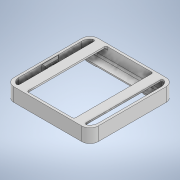
# Autodesk Inventor part: intercom_suport
Saved by Autodesk Inventor 2022.6 (Build 266554000, 554)
## iProperties
Created: 2026-04-23
Part Number: intercom_suport
Material: Generic
Document SubType Name: Modeling
Designer: Dragos Macovei
Density: 1 g/cm^3
Appearance: Default
Author: Dragos Macovei
Autodesk Inventor part; units mm, degrees
ref_plane "YZ Plane" through (0, 0, 0) normal (1, 0, 0) x (0, 1, 0)
ref_plane "XZ Plane" through (0, 0, 0) normal (0, 1, 0) x (-1, 0, 0)
ref_plane "XY Plane" through (0, 0, 0) normal (0, 0, 1) x (1, 0, 0)
sketch "Sketch1" plane through (0, 0, 0) normal (0, 1, 0) x (-1, 0, 0)
  line L0 (40.7008, 47.8646) -> (40.7008, 132.8646)
  line L1 (30.7008, 142.8646) -> (-54.2992, 142.8646)
  line L2 (40.7008, 37.8646) -> (38.7008, 37.8646)
  line L3 (-64.2992, 140.8646) -> (-64.2992, 142.8646)
  line L4 (-64.2992, 132.8646) -> (-64.2992, 47.8646)
  line L5 (-54.2992, 37.8646) -> (30.7008, 37.8646)
  arc A0 (-54.2992, 142.8646) -> (-64.2992, 132.8646) centre (-54.2992, 132.8646) ccw
  arc A1 (-64.2992, 47.8646) -> (-54.2992, 37.8646) centre (-54.2992, 47.8646) ccw
  line L6 (40.7008, 132.8646) -> (40.7008, 132.8646)
  line L7 (30.7008, 142.8646) -> (23.8305, 142.8646)
  arc A2 (40.7008, 132.8646) -> (30.7008, 142.8646) centre (30.7008, 132.8646) ccw
  arc A3 (30.7008, 37.8646) -> (40.7008, 47.8646) centre (30.7008, 47.8646) ccw
  line L8 (37.7008, 129.8646) -> (37.7008, 50.8646)
  line L9 (27.7008, 40.8646) -> (-51.2992, 40.8646)
  line L10 (-61.2992, 50.8646) -> (-61.2992, 93.3869)
  line L11 (-61.2992, 93.3869) -> (-61.2992, 129.8646)
  line L12 (-51.2992, 139.8646) -> (27.7008, 139.8646)
  arc A4 (37.7008, 129.8646) -> (27.7008, 139.8646) centre (27.7008, 129.8646) ccw
  arc A5 (-51.2992, 139.8646) -> (-61.2992, 129.8646) centre (-51.2992, 129.8646) ccw
  arc A6 (-61.2992, 50.8646) -> (-51.2992, 40.8646) centre (-51.2992, 50.8646) ccw
  arc A7 (27.7008, 40.8646) -> (37.7008, 50.8646) centre (27.7008, 50.8646) ccw
  point P0 (-11.7992, 142.8646)
  point P1 (-61.2992, 139.8646)
  dimension "d37" = 10
  dimension "d38" = 10
  dimension "d39" = 105
  dimension "d40" = 105
  dimension "d41" = 10
  dimension "d42" = 10
  dimension "d43" = 3
  dimension "d44" = 3
  dimension "d45" = 3
  dimension "d46" = 3
  dimension "d47" = 10
  constraints: 26 end point, 16 point on circle, 16 tangent, 8 centre point, 8 point on line, 5 perpendicular, 4 vertical, 3 equal radius, 1 horizontal, 1 midpoint
  measures "d37" radius of A0
  measures "d38" radius of A1
  measures "d39" distance between parallel lines of L4 L0
  measures "d40" distance from line of L5 point (-11.799, 142.865)
  measures "d41" radius of A2
  measures "d42" radius of A3
  measures "d43" distance between parallel lines of L1 L12
  measures "d44" distance between parallel lines of L0 L8
  measures "d45" distance between parallel lines of L5 L9
  measures "d46" distance between parallel lines of L4 L10
  measures "d47" radius of A4
extrude "Extrusion1" add sketch "Sketch1" along normal blind 17
sketch "Sketch2" plane through (0, 0, 0) normal (0, -1, 0) x (1, 0, 0)
  line L0 (-30.7008, 142.8646) -> (54.2992, 142.8646) projected
  arc A0 (-30.7008, 142.8646) -> (-40.7008, 132.8646) centre (-30.7008, 132.8646) ccw projected
  line L1 (-40.7008, 47.8646) -> (-40.7008, 132.8646) projected
  arc A1 (-40.7008, 47.8646) -> (-30.7008, 37.8646) centre (-30.7008, 47.8646) ccw projected
  line L2 (54.2992, 37.8646) -> (-30.7008, 37.8646) projected
  arc A2 (54.2992, 37.8646) -> (64.2992, 47.8646) centre (54.2992, 47.8646) ccw projected
  line L3 (64.2992, 132.8646) -> (64.2992, 47.8646) projected
  arc A3 (64.2992, 132.8646) -> (54.2992, 142.8646) centre (54.2992, 132.8646) ccw projected
  line L4 (51.2992, 139.8646) -> (-27.7008, 139.8646) projected
  arc A4 (61.2992, 129.8646) -> (51.2992, 139.8646) centre (51.2992, 129.8646) ccw projected
  line L5 (61.2992, 50.8646) -> (61.2992, 129.8646) projected
  arc A5 (51.2992, 40.8646) -> (61.2992, 50.8646) centre (51.2992, 50.8646) ccw projected
  line L6 (-27.7008, 40.8646) -> (51.2992, 40.8646) projected
  arc A6 (-37.7008, 50.8646) -> (-27.7008, 40.8646) centre (-27.7008, 50.8646) ccw projected
  line L7 (-37.7008, 129.8646) -> (-37.7008, 50.8646) projected
  arc A7 (-27.7008, 139.8646) -> (-37.7008, 129.8646) centre (-27.7008, 129.8646) ccw projected
  line L8 (-30.7008, 142.8646) -> (54.2992, 142.8646)
  line L9 (61.2992, 140.0061) -> (61.2992, 127.8646)
  line L10 (61.2992, 127.8646) -> (-37.7008, 127.8646)
  line L11 (-37.7008, 127.8646) -> (-37.7008, 140.0061)
  line L12 (54.2992, 37.8646) -> (-30.7008, 37.8646)
  line L13 (-40.7008, 52.8646) -> (64.2992, 52.8646)
  point P0 (0, 0)
  point P1 (61.2992, 107.224)
  point P2 (-37.7008, 107.224)
  point P3 (61.2992, 52.8646)
  point P4 (-37.7008, 52.8646)
  dimension "d49" = 15
  dimension "d65" = 0
  dimension "d66" = 15
  constraints: 12 end point, 6 point on circle, 3 parallel, 3 point on line, 2 horizontal, 1 perpendicular
  measures "d49" distance between parallel lines of L10 L8
  measures "d65" distance between parallel lines of L0 L8
  measures "d66" distance between parallel lines of L12 L13
extrude "Extrusion2" add sketch "Sketch2" against normal blind 2 contours A7 L4 A4 L5 L10 L7 | L13 L5 A5 L6 A6 L7
fillet "Fillet1" radius 2 10 edges at (-37.7008, 2, 128.8646) (61.2992, 2, 128.8646) (61.2992, 1, 127.8646) (-37.7008, 1, 127.8646) (61.2992, 9.5, 129.8646) (-37.7008, 9.5, 129.8646) (-37.7008, 2, 51.8646) (61.2992, 2, 51.8646) (61.2992, 9.5, 50.8646) (-37.7008, 9.5, 50.8646)
sketch "Sketch4" plane through (0, 17, 0) normal (0, 1, 0) x (1, 0, 0)
  line L0 (-30.7008, -142.8646) -> (54.2992, -142.8646) projected
  arc A0 (54.2992, -142.8646) -> (64.2992, -132.8646) centre (54.2992, -132.8646) ccw projected
  line L1 (64.2992, -132.8646) -> (64.2992, -47.8646) projected
  arc A1 (64.2992, -47.8646) -> (54.2992, -37.8646) centre (54.2992, -47.8646) ccw projected
  line L2 (54.2992, -37.8646) -> (-30.7008, -37.8646) projected
  arc A2 (-30.7008, -37.8646) -> (-40.7008, -47.8646) centre (-30.7008, -47.8646) ccw projected
  line L3 (-40.7008, -47.8646) -> (-40.7008, -132.8646) projected
  arc A3 (-40.7008, -132.8646) -> (-30.7008, -142.8646) centre (-30.7008, -132.8646) ccw projected
  line L4 (51.2992, -139.8646) -> (-27.7008, -139.8646) projected
  arc A4 (-37.7008, -129.8646) -> (-27.7008, -139.8646) centre (-27.7008, -129.8646) ccw projected
  line L5 (-37.7008, -129.8646) -> (-37.7008, -50.8646) projected
  arc A5 (-27.7008, -40.8646) -> (-37.7008, -50.8646) centre (-27.7008, -50.8646) ccw projected
  line L6 (-27.7008, -40.8646) -> (51.2992, -40.8646) projected
  arc A6 (61.2992, -50.8646) -> (51.2992, -40.8646) centre (51.2992, -50.8646) ccw projected
  line L7 (61.2992, -50.8646) -> (61.2992, -129.8646) projected
  arc A7 (51.2992, -139.8646) -> (61.2992, -129.8646) centre (51.2992, -129.8646) ccw projected
  line L8 (53.2992, -142.8646) -> (41.2992, -142.8646)
  line L9 (41.2992, -142.8646) -> (41.2992, -37.8646)
  line L10 (41.2992, -37.8646) -> (53.2992, -37.8646)
  line L11 (53.2992, -37.8646) -> (53.2992, -142.8646)
  line L12 (-17.7008, -142.8646) -> (-29.7008, -142.8646)
  line L13 (-29.7008, -142.8646) -> (-29.7008, -37.8646)
  line L14 (-29.7008, -37.8646) -> (-17.7008, -37.8646)
  line L15 (-17.7008, -37.8646) -> (-17.7008, -142.8646)
  point P0 (0, 0)
  point P1 (64.2992, -90.3646)
  point P2 (47.2992, -142.8646)
  point P3 (47.2992, -37.8646)
  point P4 (-17.7008, -139.8646)
  point P5 (-17.7008, -40.8646)
  point P6 (-29.7008, -41.0667)
  point P7 (-29.7008, -139.6626)
  point P8 (53.2992, -139.6626)
  point P9 (53.2992, -41.0667)
  point P10 (41.2992, -40.8646)
  point P11 (41.2992, -139.8646)
  dimension "d55" = 23
  dimension "d56" = 23
  dimension "d57" = 12
  dimension "d58" = 12
  dimension "d59" = 0
  dimension "d60" = 0
  dimension "d61" = 0
  dimension "d62" = 0
  constraints: 16 end point, 4 parallel, 3 midpoint, 2 horizontal, 2 perpendicular
  measures "d55" distance from line of L9 point (64.299, -90.365)
  measures "d56" distance between parallel lines of L3 L15
  measures "d57" distance between parallel lines of L9 L11
  measures "d58" distance between parallel lines of L13 L15
  measures "d59" distance from line of L0 point (47.299, -142.865)
  measures "d60" distance between parallel lines of L0 L12
  measures "d61" distance from line of L2 point (47.299, -37.865)
  measures "d62" distance between parallel lines of L2 L14
extrude "Extrusion4" add sketch "Sketch4" against normal blind 2 contours L13 A5 L6 L15 L4 A4 | L9 L6 A6 L11 A7 L4
fillet "Fillet2" radius 2 16 edges at (-28.7058, 15, 139.814) (-22.7008, 15, 139.8646) (-17.7008, 16, 139.8646) (-29.7008, 16, 139.6626) (41.2992, 16, 139.8646) (52.3043, 15, 139.814) (46.2992, 15, 139.8646) (53.2992, 16, 139.6626) (41.2992, 16, 40.8646) (52.3043, 15, 40.9153) (46.2992, 15, 40.8646) (53.2992, 16, 41.0667) (-17.7008, 16, 40.8646) (-28.7058, 15, 40.9153) (-22.7008, 15, 40.8646) (-29.7008, 16, 41.0667)
sketch "Sketch5" plane through (0, 0, 0) normal (0, -1, 0) x (1, 0, 0)
  line L0 (-30.7008, 142.8646) -> (54.2992, 142.8646) projected
  arc A0 (-30.7008, 142.8646) -> (-40.7008, 132.8646) centre (-30.7008, 132.8646) ccw projected
  line L1 (-40.7008, 47.8646) -> (-40.7008, 132.8646) projected
  arc A1 (-40.7008, 47.8646) -> (-30.7008, 37.8646) centre (-30.7008, 47.8646) ccw projected
  line L2 (54.2992, 37.8646) -> (-30.7008, 37.8646) projected
  arc A2 (54.2992, 37.8646) -> (64.2992, 47.8646) centre (54.2992, 47.8646) ccw projected
  line L3 (64.2992, 132.8646) -> (64.2992, 47.8646) projected
  arc A3 (64.2992, 132.8646) -> (54.2992, 142.8646) centre (54.2992, 132.8646) ccw projected
  line L4 (61.2992, 52.8646) -> (61.2992, 125.8646) projected
  line L5 (61.2992, 52.8646) -> (-37.7008, 52.8646) projected
  line L6 (-37.7008, 125.8646) -> (-37.7008, 52.8646) projected
  arc A4 (-35.7008, 127.8646) -> (-37.7008, 125.8646) centre (-35.7008, 125.8646) ccw projected
  line L7 (-35.7008, 127.8646) -> (59.2992, 127.8646) projected
  arc A5 (61.2992, 125.8646) -> (59.2992, 127.8646) centre (59.2992, 125.8646) ccw projected
  arc A6 (-32.7008, 138.5249) -> (-37.7008, 129.8646) centre (-27.7008, 129.8646) ccw projected
  line L8 (-37.7008, 129.8646) -> (-37.7008, 50.8646) projected
  arc A7 (-37.7008, 50.8646) -> (-32.7008, 42.2044) centre (-27.7008, 50.8646) ccw projected
  arc A8 (-32.7008, 42.2044) -> (-29.7008, 43.9364) centre (-31.7008, 43.9364) ccw projected
  line L9 (-29.7008, 43.9364) -> (-29.7008, 136.7929) projected
  arc A9 (-29.7008, 136.7929) -> (-32.7008, 138.5249) centre (-31.7008, 136.7929) ccw projected
  line L10 (-17.7008, 137.8646) -> (-17.7008, 42.8646) projected
  arc A10 (-17.7008, 42.8646) -> (-15.7008, 40.8646) centre (-15.7008, 42.8646) ccw projected
  line L11 (-15.7008, 40.8646) -> (39.2992, 40.8646) projected
  arc A11 (39.2992, 40.8646) -> (41.2992, 42.8646) centre (39.2992, 42.8646) ccw projected
  line L12 (41.2992, 42.8646) -> (41.2992, 137.8646) projected
  arc A12 (41.2992, 137.8646) -> (39.2992, 139.8646) centre (39.2992, 137.8646) ccw projected
  line L13 (39.2992, 139.8646) -> (-15.7008, 139.8646) projected
  arc A13 (-15.7008, 139.8646) -> (-17.7008, 137.8646) centre (-15.7008, 137.8646) ccw projected
  line L14 (-30.7008, 142.8646) -> (54.2992, 142.8646) projected
  arc A14 (64.2992, 132.8646) -> (54.2992, 142.8646) centre (54.2992, 132.8646) ccw projected
  line L15 (64.2992, 132.8646) -> (64.2992, 47.8646) projected
  arc A15 (54.2992, 37.8646) -> (64.2992, 47.8646) centre (54.2992, 47.8646) ccw projected
  line L16 (54.2992, 37.8646) -> (-30.7008, 37.8646) projected
  arc A16 (-40.7008, 47.8646) -> (-30.7008, 37.8646) centre (-30.7008, 47.8646) ccw projected
  line L17 (-40.7008, 47.8646) -> (-40.7008, 132.8646) projected
  arc A17 (-30.7008, 142.8646) -> (-40.7008, 132.8646) centre (-30.7008, 132.8646) ccw projected
  line L18 (53.2992, 136.7929) -> (53.2992, 43.9364) projected
  arc A18 (53.2992, 43.9364) -> (56.2992, 42.2044) centre (55.2992, 43.9364) ccw projected
  arc A19 (56.2992, 42.2044) -> (61.2992, 50.8646) centre (51.2992, 50.8646) ccw projected
  line L19 (61.2992, 50.8646) -> (61.2992, 129.8646) projected
  arc A20 (61.2992, 129.8646) -> (56.2992, 138.5249) centre (51.2992, 129.8646) ccw projected
  arc A21 (56.2992, 138.5249) -> (53.2992, 136.7929) centre (55.2992, 136.7929) ccw projected
  point P0 (0, 0)
  point P1 (53.2992, 127.8646)
  point P2 (53.2992, 52.8646)
  point P3 (-29.7008, 52.8646)
  point P4 (-29.7008, 127.8646)
  point P5 (41.2992, 52.8646)
  point P6 (-17.7008, 52.8646)
  point P7 (-17.7008, 127.8646)
  point P8 (41.2992, 127.8646)
extrude "Extrusion5" cut sketch "Sketch5" against normal blind 0.5 contours L19 A19 A18 L18 L5 | A5 L7 L18 A21 A20 L19 | L12 A11 L11 A10 L10 L5 | L7 L10 A13 L13 A12 L12 | L9 A8 A7 L8 L5 | L7 A4 L8 A6 A9 L9
sketch "Sketch6" plane through (0, 15, 0) normal (0, -1, 0) x (1, 0, 0)
  arc A0 (-29.8573, 43.1608) -> (-27.7008, 42.8646) centre (-27.7008, 50.8646) ccw projected
  line L0 (-17.7008, 42.8646) -> (-27.7008, 42.8646) projected
  line L1 (-17.7008, 42.8646) -> (-17.7008, 137.8646) projected
  line L2 (-27.7008, 137.8646) -> (-17.7008, 137.8646) projected
  arc A1 (-27.7008, 137.8646) -> (-29.8573, 137.5685) centre (-27.7008, 129.8646) ccw projected
  arc A2 (-29.7008, 136.7929) -> (-29.8573, 137.5685) centre (-31.7008, 136.7929) ccw projected
  line L3 (-29.7008, 136.7929) -> (-29.7008, 43.9364) projected
  arc A3 (-29.8573, 43.1608) -> (-29.7008, 43.9364) centre (-31.7008, 43.9364) ccw projected
  arc A4 (51.2992, 42.8646) -> (53.4558, 43.1608) centre (51.2992, 50.8646) ccw projected
  arc A5 (53.2992, 43.9364) -> (53.4558, 43.1608) centre (55.2992, 43.9364) ccw projected
  line L4 (53.2992, 43.9364) -> (53.2992, 136.7929) projected
  arc A6 (53.4558, 137.5685) -> (53.2992, 136.7929) centre (55.2992, 136.7929) ccw projected
  arc A7 (53.4558, 137.5685) -> (51.2992, 137.8646) centre (51.2992, 129.8646) ccw projected
  line L5 (41.2992, 137.8646) -> (51.2992, 137.8646) projected
  line L6 (41.2992, 137.8646) -> (41.2992, 42.8646) projected
  line L7 (51.2992, 42.8646) -> (41.2992, 42.8646) projected
  line L8 (48.2992, 37.8646) -> (46.2992, 37.8646)
  line L9 (46.2992, 37.8646) -> (46.2992, 142.8646)
  line L10 (46.2992, 142.8646) -> (48.2992, 142.8646)
  line L11 (48.2992, 142.8646) -> (48.2992, 37.8646)
  line L12 (-22.7008, 142.8646) -> (-24.7008, 142.8646)
  line L13 (-24.7008, 142.8646) -> (-24.7008, 37.8646)
  line L14 (-24.7008, 37.8646) -> (-22.7008, 37.8646)
  line L15 (-22.7008, 37.8646) -> (-22.7008, 142.8646)
  line L16 (-30.7008, 142.8646) -> (54.2992, 142.8646) projected
  line L17 (54.2992, 37.8646) -> (-30.7008, 37.8646) projected
  point P0 (0, 0)
  point P1 (48.2992, 42.8646)
  point P2 (48.2992, 137.8646)
  point P3 (46.2992, 137.8646)
  point P4 (46.2992, 42.8646)
  dimension "d71" = 5
  dimension "d72" = 5
  dimension "d74" = 2
  dimension "d75" = 2
  dimension "d78" = 0
  dimension "d79" = 0
  dimension "d80" = 0
  constraints: 16 end point, 4 parallel, 2 horizontal, 2 perpendicular, 1 point on line
  measures "d71" distance between parallel lines of L3 L13
  measures "d72" distance between parallel lines of L6 L9
  measures "d74" distance between parallel lines of L9 L11
  measures "d75" distance between parallel lines of L13 L15
  measures "d78" distance between parallel lines of L16 L10
  measures "d79" distance between parallel lines of L17 L8
  measures "d80" distance between parallel lines of L17 L14
extrude "Extrusion6" add sketch "Sketch6" along normal blind 1.5 contours L13 L2 L15 L0 | L0 L15 L14 L13 | L13 L12 L15 L2 | L9 L7 L11 L8 | L9 L5 L11 L7 | L10 L11 L5 L9
sketch "Sketch7" plane through (-40.7008, 0, 47.8646) normal (-1, 0, 0) x (0, 0, 1)
  line L0 (0, 0) -> (85, 0) projected
  line L1 (85, 0) -> (85, 17) projected
  line L2 (0, 17) -> (85, 17) projected
  line L3 (0, 0) -> (0, 17) projected
  line L4 (3, 2) -> (5, 2) projected
  line L5 (-5, 2) -> (3, 2) projected
  line L6 (3, 2) -> (-5, 2) projected
  line L7 (5, 2) -> (3, 2) projected
  line L8 (82, 2) -> (80, 2) projected
  line L9 (90, 2) -> (82, 2) projected
  line L10 (82, 2) -> (90, 2) projected
  line L11 (80, 2) -> (82, 2) projected
  line L12 (-5, 15) -> (90, 15) projected
  line L13 (37, 11.5) -> (48, 11.5)
  line L14 (48, 11.5) -> (48, 5.5)
  line L15 (48, 5.5) -> (37, 5.5)
  line L16 (37, 5.5) -> (37, 11.5)
  line L17 (-10, 0) -> (-10, 17) projected
  point P0 (-47.8646, 0)
  point P1 (37, 8.5)
  point P2 (42.5, 5.5)
  point P3 (-10, 8.5)
  dimension "d81" = 11
  dimension "d82" = 6
  dimension "d83" = 5.5
  dimension "d84" = 47
  constraints: 8 end point, 3 midpoint, 2 parallel, 1 horizontal, 1 perpendicular
  measures "d81" distance from line of L14 point (37, 8.5)
  measures "d82" distance between parallel lines of L15 L13
  measures "d83" distance from line of L0 point (42.5, 5.5)
  measures "d84" distance of point (37, 8.5) point (-10, 8.5)
extrude "Extrusion7" cut sketch "Sketch7" against normal blind 17.5 contours L13 L14 L15 L16
sketch "Sketch8" plane through (-40.7008, 0, 47.8646) normal (-1, 0, 0) x (0, 0, 1)
  line L0 (48, 11.5) -> (48, 5.5) projected
  line L1 (48, 5.5) -> (37, 5.5) projected
  line L2 (37, 5.5) -> (37, 11.5) projected
  line L3 (37, 11.5) -> (48, 11.5) projected
  line L4 (0, 0) -> (85, 0) projected
  line L5 (85, 0) -> (85, 17) projected
  line L6 (0, 17) -> (85, 17) projected
  line L7 (0, 0) -> (0, 17) projected
  line L8 (48, 11.5) -> (53, 11.5)
  line L9 (53, 11.5) -> (53, 5.5)
  line L10 (53, 5.5) -> (48, 5.5)
  line L11 (48, 5.5) -> (48, 11.5)
  line L12 (37, 11.5) -> (48, 11.5) projected
  line L13 (37, 11.5) -> (32, 11.5)
  line L14 (32, 11.5) -> (32, 5.5)
  line L15 (32, 5.5) -> (37, 5.5)
  line L16 (37, 5.5) -> (37, 11.5)
  point P0 (-47.8646, 0)
  point P1 (32, 8.5)
  point P2 (37, 8.5)
  dimension "d88" = 5
  dimension "d89" = 5
  constraints: 16 end point, 4 parallel, 2 horizontal, 2 midpoint, 2 perpendicular, 1 point on line
  measures "d88" distance between parallel lines of L9 L0
  measures "d89" distance of point (32, 8.5) point (37, 8.5)
extrude "Extrusion8" cut sketch "Sketch8" against normal blind 0.5 contours L8 L9 L10 L0 | L2 L15 L14 L13
sketch "Sketch9" plane through (-37.7008, 17, 129.8646) normal (1, 0, 0) x (0, 0, -1)
  line L0 (82, -17) -> (-3, -17) projected
  line L1 (-3, -17) -> (-3, 0) projected
  line L2 (82, 0) -> (-3, 0) projected
  line L3 (82, -17) -> (82, 0) projected
  line L4 (50, -5.5) -> (29, -5.5) projected
  line L5 (29, -5.5) -> (29, -11.5) projected
  line L6 (29, -11.5) -> (50, -11.5) projected
  line L7 (50, -11.5) -> (50, -5.5) projected
  line L8 (29, -5.5) -> (29, -11.5) projected
  line L9 (34, -5.5) -> (29, -5.5) projected
  line L10 (34, -11.5) -> (34, -5.5) projected
  line L11 (29, -11.5) -> (34, -11.5) projected
  line L12 (50, -11.5) -> (50, -5.5) projected
  line L13 (45, -11.5) -> (50, -11.5) projected
  line L14 (45, -5.5) -> (45, -11.5) projected
  line L15 (50, -5.5) -> (45, -5.5) projected
  line L16 (31, -2.5) -> (48, -2.5)
  line L17 (48, -2.5) -> (48, -14.5)
  line L18 (48, -14.5) -> (31, -14.5)
  line L19 (31, -14.5) -> (31, -2.5)
  point P0 (129.8646, -17)
  point P1 (39.5, -11.5)
  dimension "d98" = 3
  dimension "d99" = 3
  dimension "d100" = 3
  dimension "d101" = 3
  constraints: 8 end point, 2 parallel, 1 horizontal, 1 midpoint, 1 perpendicular
  measures "d98" distance between parallel lines of L4 L16
  measures "d99" distance between parallel lines of L19 L10
  measures "d100" distance from line of L18 point (39.5, -11.5)
  measures "d101" distance between parallel lines of L14 L17
extrude "Extrusion9" add sketch "Sketch9" along normal blind 2 contours L4 L19 L16 L17 | L4 L17 L6 L14 | L10 L6 L19 L4 | L6 L17 L18 L19
fillet "Fillet3" radius 2 4 edges at (-37.7008, 14.5, 90.3646) (-37.7008, 8.5, 81.8646) (-37.7008, 2.5, 90.3646) (-37.7008, 8.5, 98.8646)
body "Solid1"
